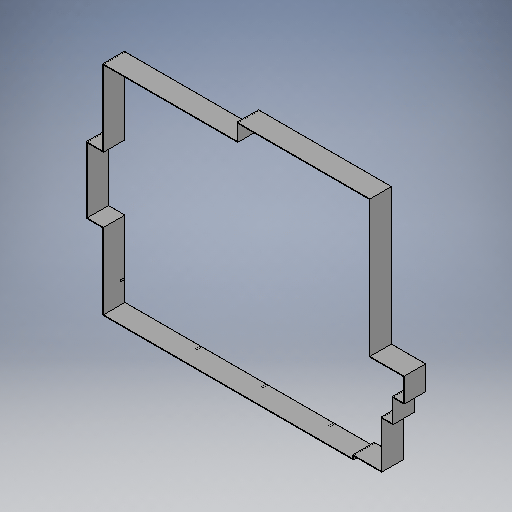
# Autodesk Inventor part: Factory_Outer_Walls
Saved by Autodesk Inventor 2026.2 (Build 302298000, 298)
## iProperties
Part Number: Factory_Outer_Walls
Material: Generic
Document SubType Name: Modeling
Designer: Jacob
Appearance: Default
Author: Jacob
Autodesk Inventor part; units mm, degrees
ref_plane "YZ Plane" through (0, 0, 0) normal (1, 0, 0) x (0, 1, 0)
ref_plane "XZ Plane" through (0, 0, 0) normal (0, 1, 0) x (-1, 0, 0)
ref_plane "XY Plane" through (0, 0, 0) normal (0, 0, 1) x (1, 0, 0)
sketch "Sketch1" plane through (0, 0, 0) normal (0, 0, 1) x (1, 0, 0)
  line L0 (8352.05, 155.35) -> (124907.95, 155.35)
  line L1 (124907.95, 155.35) -> (124907.95, 461.25)
  line L2 (124907.95, 461.25) -> (8352.05, 461.25)
  line L3 (8352.05, 461.25) -> (8352.05, 155.35)
  line L4 (124602.05, 155.35) -> (124907.95, 155.35)
  line L5 (124907.95, 155.35) -> (124907.95, 2079.25)
  line L6 (124907.95, 2079.25) -> (124602.05, 2079.25)
  line L7 (124602.05, 2079.25) -> (124602.05, 155.35)
  line L8 (124602.05, 1773.35) -> (138017.65, 1773.35)
  line L9 (138017.65, 1773.35) -> (138017.65, 2079.25)
  line L10 (138017.65, 2079.25) -> (124602.05, 2079.25)
  line L11 (124602.05, 2079.25) -> (124602.05, 1773.35)
  line L12 (137711.75, 1773.35) -> (138017.65, 1773.35)
  line L13 (138017.65, 1773.35) -> (138017.65, 23827.35)
  line L14 (138017.65, 23827.35) -> (137711.75, 23827.35)
  line L15 (137711.75, 23827.35) -> (137711.75, 1773.35)
  line L16 (137711.75, 23521.45) -> (143237.45, 23521.45)
  line L17 (143237.45, 23521.45) -> (143237.45, 23827.35)
  line L18 (143237.45, 23827.35) -> (137711.75, 23827.35)
  line L19 (137711.75, 23827.35) -> (137711.75, 23521.45)
  line L20 (142931.55, 23521.45) -> (143237.45, 23521.45)
  line L21 (143237.45, 23521.45) -> (143237.45, 34712.65)
  line L22 (143237.45, 34712.65) -> (142931.55, 34712.65)
  line L23 (142931.55, 34712.65) -> (142931.55, 23521.45)
  line L24 (142931.55, 34406.75) -> (148457.25, 34406.75)
  line L25 (148457.25, 34406.75) -> (148457.25, 34712.65)
  line L26 (148457.25, 34712.65) -> (142931.55, 34712.65)
  line L27 (142931.55, 34712.65) -> (142931.55, 34406.75)
  line L28 (148151.35, 34406.75) -> (148457.25, 34406.75)
  line L29 (148457.25, 34406.75) -> (148457.25, 45636.15)
  line L30 (148457.25, 45636.15) -> (148151.35, 45636.15)
  line L31 (148151.35, 45636.15) -> (148151.35, 34406.75)
  line L32 (132250.05, 45330.25) -> (148457.25, 45330.25)
  line L33 (148457.25, 45330.25) -> (148457.25, 45636.15)
  line L34 (148457.25, 45636.15) -> (132250.05, 45636.15)
  line L35 (132250.05, 45636.15) -> (132250.05, 45330.25)
  line L36 (132250.05, 45330.25) -> (132555.95, 45330.25)
  line L37 (132555.95, 45330.25) -> (132555.95, 109063.25)
  line L38 (132555.95, 109063.25) -> (132250.05, 109063.25)
  line L39 (132250.05, 109063.25) -> (132250.05, 45330.25)
  line L40 (70772.65, 108757.35) -> (132555.95, 108757.35)
  line L41 (132555.95, 108757.35) -> (132555.95, 109063.25)
  line L42 (132555.95, 109063.25) -> (70772.65, 109063.25)
  line L43 (70772.65, 109063.25) -> (70772.65, 108757.35)
  line L44 (70772.65, 101109.35) -> (71078.55, 101109.35)
  line L45 (71078.55, 101109.35) -> (71078.55, 109063.25)
  line L46 (71078.55, 109063.25) -> (70772.65, 109063.25)
  line L47 (70772.65, 109063.25) -> (70772.65, 101109.35)
  line L48 (8352.05, 101109.35) -> (71078.55, 101109.35)
  line L49 (71078.55, 101109.35) -> (71078.55, 101415.25)
  line L50 (71078.55, 101415.25) -> (8352.05, 101415.25)
  line L51 (8352.05, 101415.25) -> (8352.05, 101109.35)
  line L52 (8352.05, 65928.45) -> (8657.95, 65928.45)
  line L53 (8657.95, 65928.45) -> (8657.95, 101415.25)
  line L54 (8657.95, 101415.25) -> (8352.05, 101415.25)
  line L55 (8352.05, 101415.25) -> (8352.05, 65928.45)
  line L56 (704.05, 65928.45) -> (8657.95, 65928.45)
  line L57 (8657.95, 65928.45) -> (8657.95, 66234.35)
  line L58 (8657.95, 66234.35) -> (704.05, 66234.35)
  line L59 (704.05, 66234.35) -> (704.05, 65928.45)
  line L60 (704.05, 35336.35) -> (1009.95, 35336.35)
  line L61 (1009.95, 35336.35) -> (1009.95, 66234.35)
  line L62 (1009.95, 66234.35) -> (704.05, 66234.35)
  line L63 (704.05, 66234.35) -> (704.05, 35336.35)
  line L64 (704.05, 35336.35) -> (8657.95, 35336.35)
  line L65 (8657.95, 35336.35) -> (8657.95, 35642.25)
  line L66 (8657.95, 35642.25) -> (704.05, 35642.25)
  line L67 (704.05, 35642.25) -> (704.05, 35336.35)
  line L68 (8352.05, 155.35) -> (8657.95, 155.35)
  line L69 (8657.95, 155.35) -> (8657.95, 35642.25)
  line L70 (8657.95, 35642.25) -> (8352.05, 35642.25)
  line L71 (8352.05, 35642.25) -> (8352.05, 155.35)
  constraints: 144 end point, 36 parallel, 18 horizontal, 18 perpendicular
extrude "Extrusion1" add sketch "Sketch1" along normal blind 10000 contours L3 L2 L69 L0 | L69 L2 L7 L0 | L71 L64 L69 L2 | L7 L2 L1 L0 | L71 L66 L65 L64 | L64 L61 L66 L71 | L7 L8 L5 L2 | L60 L63 L66 L61 | L7 L6 L5 L8 | L66 L63 L56 L61 | L5 L10 L15 L8 | L61 L58 L55 L56 | L56 L59 L58 L61 | L15 L10 L9 L8 | L55 L58 L53 L52 | L15 L16 L13 L10 | L55 L48 L53 L58 | L15 L14 L13 L16 | L51 L50 L53 L48 | L13 L18 L23 L16 | L53 L50 L47 L48 | L23 L18 L17 L16 | L47 L50 L45 L44 | L23 L24 L21 L18 | L47 L40 L45 L50 | L23 L22 L21 L24 | L43 L42 L45 L40 | L21 L26 L31 L24 | L45 L42 L39 L40 | L31 L26 L25 L24 | L40 L37 L34 L39 | L39 L38 L37 L40 | L31 L32 L29 L26 | L34 L37 L32 L35 | L32 L37 L34 L31 | L31 L30 L29 L32
sketch "Sketch2" plane through (0, 0, 0) normal (0, 0, 1) x (1, 0, 0)
  line L0 (129548.5, 62429.5) -> (131809.5, 62429.5)
  line L1 (131809.5, 62429.5) -> (131809.5, 63229.5)
  line L2 (131809.5, 63229.5) -> (129548.5, 63229.5)
  line L3 (129548.5, 63229.5) -> (129548.5, 62429.5)
  constraints: 8 end point, 2 parallel, 1 horizontal, 1 perpendicular
extrude "Extrusion2" cut sketch "Sketch2" along normal blind 4500
sketch "Sketch3" plane through (0, 0, 0) normal (0, 0, 1) x (1, 0, 0)
  line L0 (9892.2, 69924.9) -> (12153.2, 69924.9)
  line L1 (12153.2, 69924.9) -> (12153.2, 70724.9)
  line L2 (12153.2, 70724.9) -> (9892.2, 70724.9)
  line L3 (9892.2, 70724.9) -> (9892.2, 69924.9)
  constraints: 8 end point, 2 parallel, 1 horizontal, 1 perpendicular
extrude "Extrusion3" cut sketch "Sketch3" along normal blind 4500
sketch "Sketch4" plane through (0, 0, 0) normal (0, 0, 1) x (1, 0, 0)
  line L0 (65332.2, 775) -> (67593.2, 775)
  line L1 (67593.2, 775) -> (67593.2, 1575)
  line L2 (67593.2, 1575) -> (65332.2, 1575)
  line L3 (65332.2, 1575) -> (65332.2, 775)
  constraints: 8 end point, 2 parallel, 1 horizontal, 1 perpendicular
extrude "Extrusion4" cut sketch "Sketch4" along normal blind 4500
sketch "Sketch5" plane through (0, 0, 0) normal (0, 0, 1) x (1, 0, 0)
  line L0 (43515.9, -707.7) -> (44315.9, -707.7)
  line L1 (44315.9, -707.7) -> (44315.9, 202.3)
  line L2 (44315.9, 202.3) -> (43515.9, 202.3)
  line L3 (43515.9, 202.3) -> (43515.9, -707.7)
  constraints: 8 end point, 2 parallel, 1 horizontal, 1 perpendicular
extrude "Extrusion5" cut sketch "Sketch5" along normal blind 2100
sketch "Sketch6" plane through (0, 0, 0) normal (0, 0, 1) x (1, 0, 0)
  line L0 (7744.8, 9778.2) -> (8654.8, 9778.2)
  line L1 (8654.8, 9778.2) -> (8654.8, 10578.2)
  line L2 (8654.8, 10578.2) -> (7744.8, 10578.2)
  line L3 (7744.8, 10578.2) -> (7744.8, 9778.2)
  constraints: 8 end point, 2 parallel, 1 horizontal, 1 perpendicular
extrude "Extrusion6" cut sketch "Sketch6" along normal blind 2100
sketch "Sketch7" plane through (0, 0, 0) normal (0, 0, 1) x (1, 0, 0)
  line L0 (74194.4, -707.7) -> (74994.4, -707.7)
  line L1 (74994.4, -707.7) -> (74994.4, 202.3)
  line L2 (74994.4, 202.3) -> (74194.4, 202.3)
  line L3 (74194.4, 202.3) -> (74194.4, -707.7)
  constraints: 8 end point, 2 parallel, 1 horizontal, 1 perpendicular
extrude "Extrusion7" cut sketch "Sketch7" along normal blind 2100
sketch "Sketch8" plane through (0, 0, 0) normal (0, 0, 1) x (1, 0, 0)
  line L0 (105429.3, -707.7) -> (106229.3, -707.7)
  line L1 (106229.3, -707.7) -> (106229.3, 202.3)
  line L2 (106229.3, 202.3) -> (105429.3, 202.3)
  line L3 (105429.3, 202.3) -> (105429.3, -707.7)
  constraints: 8 end point, 2 parallel, 1 horizontal, 1 perpendicular
extrude "Extrusion8" cut sketch "Sketch8" along normal blind 2100
sketch "Sketch9" plane through (0, 0, 0) normal (0, 0, 1) x (1, 0, 0)
  line L0 (133310.8, 556.6) -> (134110.8, 556.6)
  line L1 (134110.8, 556.6) -> (134110.8, 1466.6)
  line L2 (134110.8, 1466.6) -> (133310.8, 1466.6)
  line L3 (133310.8, 1466.6) -> (133310.8, 556.6)
  constraints: 8 end point, 2 parallel, 1 horizontal, 1 perpendicular
extrude "Extrusion9" cut sketch "Sketch9" along normal blind 2100
sketch "Sketch10" plane through (0, 0, 0) normal (0, 0, 1) x (1, 0, 0)
  line L0 (145143, 45904.4) -> (145943, 45904.4)
  line L1 (145943, 45904.4) -> (145943, 46814.4)
  line L2 (145943, 46814.4) -> (145143, 46814.4)
  line L3 (145143, 46814.4) -> (145143, 45904.4)
  constraints: 8 end point, 2 parallel, 1 horizontal, 1 perpendicular
extrude "Extrusion10" cut sketch "Sketch10" along normal blind 2100
sketch "Sketch11" plane through (0, 0, 0) normal (0, 0, 1) x (1, 0, 0)
  line L0 (117414.3, 39898.1) -> (118214.3, 39898.1)
  line L1 (118214.3, 39898.1) -> (118214.3, 40808.1)
  line L2 (118214.3, 40808.1) -> (117414.3, 40808.1)
  line L3 (117414.3, 40808.1) -> (117414.3, 39898.1)
  constraints: 8 end point, 2 parallel, 1 horizontal, 1 perpendicular
extrude "Extrusion11" cut sketch "Sketch11" along normal blind 2100
body "Solid1"
